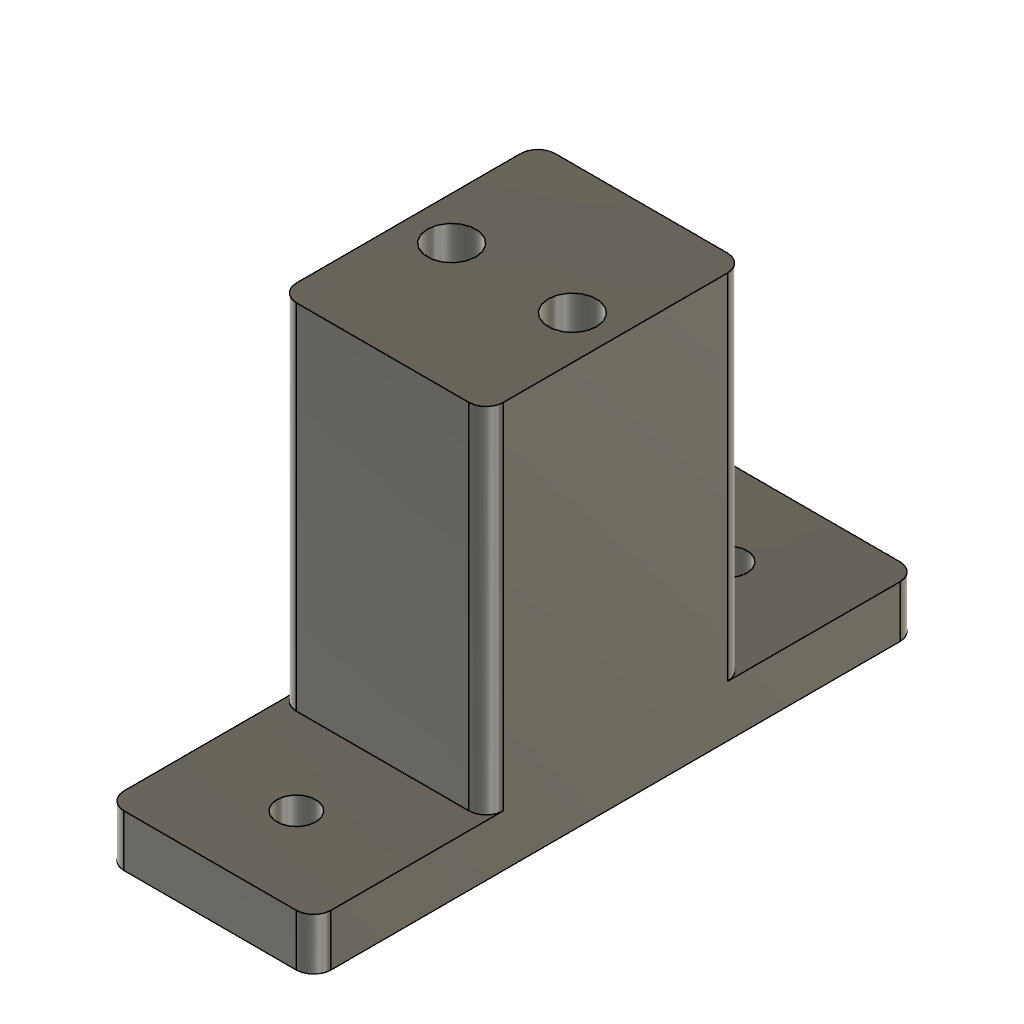
VISION_SWINE_Adapter_V1 (Autodesk Fusion 360 design; units mm, degrees)
part number: 2026-11-26-04-25-40-937
part number: 2026-11-26-04-25-41-456
Autodesk Fusion 360 part; units mm, degrees
ref_plane "WorkPlane1" through (-12, 0, 0) normal (1, 0, 0) x (0, 1, 0) in component "Adapter_V1"
ref_plane "WorkPlane2" through (0, -35, 0) normal (0, 1, 0) x (0, 0, 1) in component "Adapter_V1"
ref_plane "WorkPlane3" through (12, 0, 0) normal (1, 0, 0) x (0, 1, 0) in component "Adapter_V1"
ref_plane "WorkPlane4" through (0, 35, 0) normal (0, 1, 0) x (0, 0, 1) in component "Adapter_V1"
sketch "Sketch1" plane through (0, 0, 0) normal (0, 0, 1) x (1, 0, 0) in component "Adapter_V1"
  line L0 (-12, -35) -> (12, -35)
  line L1 (12, -35) -> (12, 35)
  line L2 (12, 35) -> (-12, 35)
  line L3 (-12, 35) -> (-12, -35)
extrude "Rectangular blank" add sketch "Sketch1" along normal blind 6 in component "Adapter_V1"
ref_plane "WorkPlane5" through (0, 0, 6) normal (0, 0, 1) x (1, 0, 0) in component "Adapter_V1"
ref_plane "WorkPlane6" through (0, -15, 0) normal (0, 1, 0) x (0, 0, 1) in component "Adapter_V1"
ref_plane "WorkPlane7" through (0, 15, 0) normal (0, 1, 0) x (0, 0, 1) in component "Adapter_V1"
sketch "Sketch2" plane through (0, 0, 6) normal (0, 0, 1) x (1, 0, 0) in component "Adapter_V1"
  line L0 (-12, -15) -> (12, -15)
  line L1 (12, -15) -> (12, 15)
  line L2 (12, 15) -> (-12, 15)
  line L3 (-12, 15) -> (-12, -15)
extrude "Central neck" add sketch "Sketch2" along normal blind 41 in component "Adapter_V1"
fillet "Rounded flange and neck corners" radius 2 8 edges at (-12, 15, 26.5) (12, 15, 26.5) (12, -15, 26.5) (-12, -15, 26.5) (-12, 35, 3) (12, 35, 3) (12, -35, 3) (-12, -35, 3) in component "Adapter_V1"
ref_plane "WorkPlane8" through (0, 25, 0) normal (0, 1, 0) x (0, 0, 1) in component "Adapter_V1"
sketch "Sketch3" plane through (0, 0, 0) normal (0, 0, 1) x (1, 0, 0) in component "Adapter_V1"
  circle A0 centre (0, 25) radius 2.25
  dimension "d34" = 4.5
  measures "d34" diameter of A0
extrude "Lower M4 clearance" cut sketch "Sketch3" along normal blind 6 in component "Adapter_V1"
ref_plane "WorkPlane9" through (0, 0, 37) normal (0, 0, 1) x (1, 0, 0) in component "Adapter_V1"
ref_plane "WorkPlane10" through (7, 0, 0) normal (1, 0, 0) x (0, 1, 0) in component "Adapter_V1"
sketch "Sketch4" plane through (0, 0, 37) normal (0, 0, 1) x (1, 0, 0) in component "Adapter_V1"
  circle A0 centre (7, 0) radius 2.8
  dimension "d41" = 5.6
  measures "d41" diameter of A0
extrude "Upper insert trial pocket" cut sketch "Sketch4" along normal blind 10 in component "Adapter_V1"
ref_plane "WorkPlane11" through (0, -25, 0) normal (0, 1, 0) x (0, 0, 1) in component "Adapter_V1"
sketch "Sketch5" plane through (0, 0, 0) normal (0, 0, 1) x (1, 0, 0) in component "Adapter_V1"
  circle A0 centre (0, -25) radius 2.25
  dimension "d46" = 4.5
  measures "d46" diameter of A0
extrude "Lower M4 clearance (1)" cut sketch "Sketch5" along normal blind 6 in component "Adapter_V1"
ref_plane "WorkPlane12" through (-7, 0, 0) normal (1, 0, 0) x (0, 1, 0) in component "Adapter_V1"
sketch "Sketch6" plane through (0, 0, 37) normal (0, 0, 1) x (1, 0, 0) in component "Adapter_V1"
  circle A0 centre (-7, 0) radius 2.8
  dimension "d51" = 5.6
  measures "d51" diameter of A0
extrude "Upper insert trial pocket (1)" cut sketch "Sketch6" along normal blind 10 in component "Adapter_V1"
component "Adapter_V1" placed x (1, 0, 0) y (0, 1, 0) z (0, 0, 1) at (0, 0, 0)
equation "avWidth = 24 mm" comment "Adapter V1 prototype"
equation "avNeck = 30 mm" comment "Adapter V1 prototype"
equation "avBase = 70 mm" comment "Adapter V1 prototype"
equation "avHeight = 47 mm" comment "Adapter V1 prototype"
equation "avFlange = 6 mm" comment "Adapter V1 prototype"
equation "avR = 2 mm" comment "Adapter V1 prototype"
equation "avBasePitch = 50 mm" comment "Adapter V1 prototype"
equation "avTopPitch = 14 mm" comment "Adapter V1 prototype"
equation "avM4Clear = 4.5 mm" comment "Adapter V1 prototype"
equation "avInsertPilot = 5.6 mm" comment "Adapter V1 prototype"
equation "avPocket = 10 mm" comment "Adapter V1 prototype"
equation "d12 = -avWidth / 2"
equation "d14 = -avBase / 2"
equation "d16 = avWidth / 2"
equation "d18 = avBase / 2"
equation "d20 = avFlange"
equation "d22 = avFlange"
equation "d24 = -avNeck / 2"
equation "d26 = avNeck / 2"
equation "d28 = avHeight - avFlange"
equation "d31 = avR"
equation "d32 = avBasePitch / 2"
equation "d34 = avM4Clear"
equation "d35 = avFlange"
equation "d37 = avHeight - avPocket"
equation "d39 = avTopPitch / 2"
equation "d41 = avInsertPilot"
equation "d42 = avPocket"
equation "d44 = -avBasePitch / 2"
equation "d46 = avM4Clear"
equation "d47 = avFlange"
equation "d49 = -avTopPitch / 2"
equation "d51 = avInsertPilot"
equation "d52 = avPocket"
